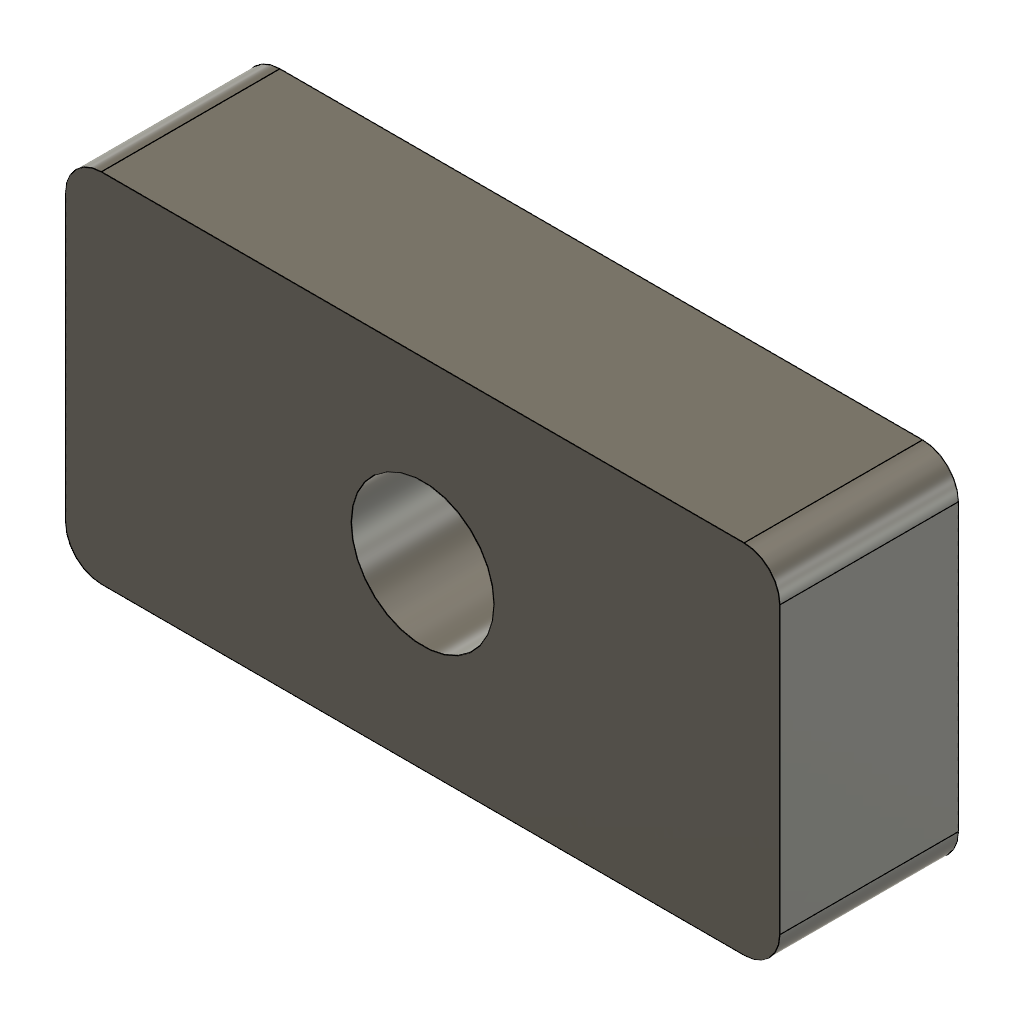
renamed_mixed (Autodesk Fusion 360 design; units mm, degrees)
part number: 2026-11-10-16-17-35-724
Autodesk Fusion 360 part; units mm, degrees
sketch "outline" plane through (0, 0, 0) normal (0, 0, 1) x (1, 0, 0)
  line L0 (0, 0) -> (20, 0)
  line L1 (20, 0) -> (20, 10)
  line L2 (20, 10) -> (0, 10)
  line L3 (0, 10) -> (0, 0)
extrude "plate" add sketch "outline" along normal blind 5
sketch "bore_sketch" plane through (0, 0, 0) normal (0, 0, 1) x (1, 0, 0)
  circle A0 centre (10, 5) radius 2
extrude "bore" cut sketch "bore_sketch" along normal through all
chamfer "top_chamfer" [suppressed]
fillet "corner_round" radius 1 4 edges at (0, 10, 2.5) (20, 10, 2.5) (20, 0, 2.5) (0, 0, 2.5)
